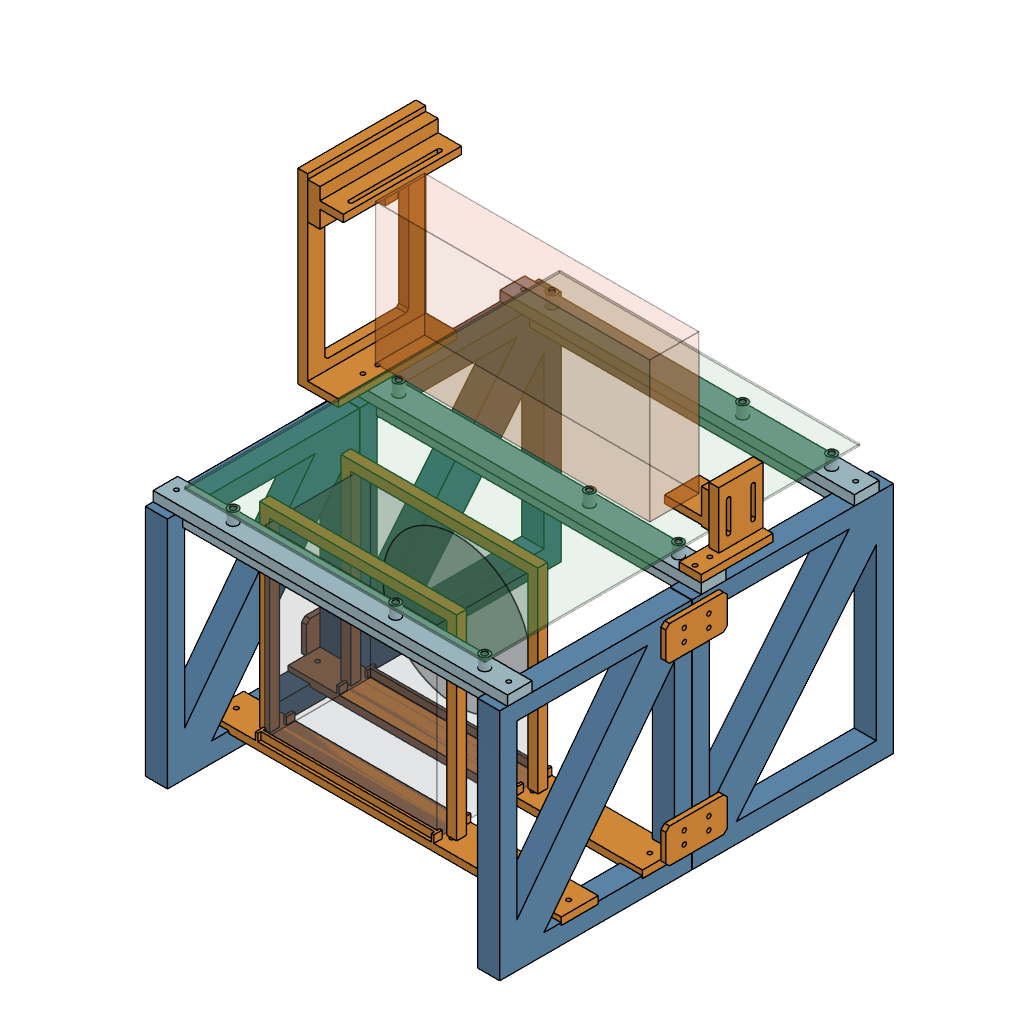
ATX_Desk_v01 (Autodesk Fusion 360 design; units mm, degrees)
part number: 2026-10-20-22-05-08-730
part number: 2026-10-20-22-08-08-339
part number: 2026-10-20-22-08-09-316
part number: 2026-10-20-22-08-11-193
part number: 2026-10-20-22-08-14-444
part number: 2026-10-20-22-08-18-650
part number: 2026-10-20-22-08-21-543
part number: 2026-10-20-22-08-24-691
part number: 2026-10-20-22-08-28-165
part number: 2026-10-20-22-08-32-235
part number: 2026-10-20-22-08-43-731
part number: 2026-10-20-22-09-05-620
part number: 2026-10-20-22-09-23-823
part number: 2026-10-20-22-09-44-105
part number: 2026-10-20-22-09-50-238
part number: 2026-10-20-22-10-13-900
part number: 2026-10-20-22-10-20-773
part number: 2026-10-20-22-10-46-637
part number: 2026-10-20-22-11-06-448
part number: 2026-10-20-22-11-11-779
part number: 2026-10-20-22-11-40-530
part number: 2026-10-20-22-11-51-657
part number: 2026-10-20-22-12-25-247
part number: 2026-10-20-22-12-53-814
part number: 2026-10-20-22-12-58-404
part number: 2026-10-20-22-13-02-654
Autodesk Fusion 360 part; units mm, degrees
(part 1 of 2)
ref_plane "工作平面1" through (0, 0, 0) normal (0, 0, 1) x (1, 0, 0) in component "01_Side_L_rear"
sketch "草图1" plane through (0, 0, 0) normal (0, 0, 1) x (1, 0, 0) in component "01_Side_L_rear"
  line L0 (-22, -10) -> (-4, -10)
  line L1 (-4, -10) -> (-4, 146)
  line L2 (-4, 146) -> (-22, 146)
  line L3 (-22, 146) -> (-22, -10)
extrude "18 mm triangulated side panel" add sketch "草图1" along normal blind 190 makes body 1 in component "01_Side_L_rear"
ref_plane "工作平面2" through (-22, 0, 0) normal (1, 0, 0) x (0, 1, 0) in component "01_Side_L_rear"
sketch "草图2" plane through (-22, 0, 0) normal (1, 0, 0) x (0, 0, -1) in component "01_Side_L_rear"
  line L0 (-36, 4) -> (-176, 4)
  line L1 (-176, 4) -> (-176, 110)
  line L2 (-176, 110) -> (-36, 4)
extrude "Upper lightening window" cut sketch "草图2" along normal blind 18 bodies 1 in component "01_Side_L_rear"
ref_plane "工作平面3" through (-22, 0, 0) normal (1, 0, 0) x (0, 1, 0) in component "01_Side_L_rear"
sketch "草图3" plane through (-22, 0, 0) normal (1, 0, 0) x (0, 0, -1) in component "01_Side_L_rear"
  line L0 (-16, 26) -> (-16, 132)
  line L1 (-16, 132) -> (-154, 132)
  line L2 (-154, 132) -> (-16, 26)
extrude "Lower lightening window" cut sketch "草图3" along normal blind 18 bodies 1 in component "01_Side_L_rear"
ref_plane "工作平面4" through (0, 0, 185.3) normal (0, 0, 1) x (1, 0, 0) in component "01_Side_L_rear"
sketch "草图4" plane through (0, 0, 185.3) normal (0, 0, 1) x (1, 0, 0) in component "01_Side_L_rear"
  circle A0 centre (-13, 6.35) radius 2.35
extrude "M3 heat insert pocket" cut sketch "草图4" along normal blind 4.7 bodies 1 in component "01_Side_L_rear"
ref_plane "工作平面5" through (0, 0, 9.3) normal (0, 0, 1) x (1, 0, 0) in component "01_Side_L_rear"
sketch "草图5" plane through (0, 0, 9.3) normal (0, 0, 1) x (1, 0, 0) in component "01_Side_L_rear"
  circle A0 centre (-13, 55) radius 2.35
extrude "M3 heat insert pocket (1)" cut sketch "草图5" along normal blind 4.7 bodies 1 in component "01_Side_L_rear"
ref_plane "工作平面6" through (0, 0, 9.3) normal (0, 0, 1) x (1, 0, 0) in component "01_Side_L_rear"
sketch "草图6" plane through (0, 0, 9.3) normal (0, 0, 1) x (1, 0, 0) in component "01_Side_L_rear"
  circle A0 centre (-13, 121) radius 2.35
extrude "M3 heat insert pocket (2)" cut sketch "草图6" along normal blind 4.7 bodies 1 in component "01_Side_L_rear"
ref_plane "工作平面7" through (-22, 0, 0) normal (1, 0, 0) x (0, 1, 0) in component "01_Side_L_rear"
sketch "草图7" plane through (-22, 0, 0) normal (1, 0, 0) x (0, 0, -1) in component "01_Side_L_rear"
  circle A0 centre (-25, 136) radius 2.35
extrude "M3 long insert side pocket" cut sketch "草图7" along normal blind 8.2 bodies 1 in component "01_Side_L_rear"
ref_plane "工作平面8" through (-22, 0, 0) normal (1, 0, 0) x (0, 1, 0) in component "01_Side_L_rear"
sketch "草图8" plane through (-22, 0, 0) normal (1, 0, 0) x (0, 0, -1) in component "01_Side_L_rear"
  circle A0 centre (-35, 136) radius 2.35
extrude "M3 long insert side pocket (1)" cut sketch "草图8" along normal blind 8.2 bodies 1 in component "01_Side_L_rear"
ref_plane "工作平面9" through (-22, 0, 0) normal (1, 0, 0) x (0, 1, 0) in component "01_Side_L_rear"
sketch "草图9" plane through (-22, 0, 0) normal (1, 0, 0) x (0, 0, -1) in component "01_Side_L_rear"
  circle A0 centre (-167.5, 136) radius 2.35
extrude "M3 long insert side pocket (2)" cut sketch "草图9" along normal blind 8.2 bodies 1 in component "01_Side_L_rear"
ref_plane "工作平面10" through (-22, 0, 0) normal (1, 0, 0) x (0, 1, 0) in component "01_Side_L_rear"
sketch "草图10" plane through (-22, 0, 0) normal (1, 0, 0) x (0, 0, -1) in component "01_Side_L_rear"
  circle A0 centre (-177.5, 136) radius 2.35
extrude "M3 long insert side pocket (3)" cut sketch "草图10" along normal blind 8.2 bodies 1 in component "01_Side_L_rear"
ref_plane "工作平面1" through (0, 0, 0) normal (0, 0, 1) x (1, 0, 0) in component "01_Side_L_front"
sketch "草图1 (2)" plane through (0, 0, 0) normal (0, 0, 1) x (1, 0, 0) in component "01_Side_L_front"
  line L0 (-22, 146.4) -> (-4, 146.4)
  line L1 (-4, 146.4) -> (-4, 310)
  line L2 (-4, 310) -> (-22, 310)
  line L3 (-22, 310) -> (-22, 146.4)
extrude "18 mm triangulated side panel'" add sketch "草图1 (2)" along normal blind 190 separate body makes body 2 in component "01_Side_L_front"
ref_plane "工作平面2" through (-22, 0, 0) normal (1, 0, 0) x (0, 1, 0) in component "01_Side_L_front"
sketch "草图2 (2)" plane through (-22, 0, 0) normal (1, 0, 0) x (0, 0, -1) in component "01_Side_L_front"
  line L0 (-36, 160.4) -> (-176, 160.4)
  line L1 (-176, 160.4) -> (-176, 274)
  line L2 (-176, 274) -> (-36, 160.4)
extrude "Upper lightening window'" cut sketch "草图2 (2)" along normal blind 18 bodies 2 in component "01_Side_L_front"
ref_plane "工作平面3" through (-22, 0, 0) normal (1, 0, 0) x (0, 1, 0) in component "01_Side_L_front"
sketch "草图3 (2)" plane through (-22, 0, 0) normal (1, 0, 0) x (0, 0, -1) in component "01_Side_L_front"
  line L0 (-16, 182.4) -> (-16, 296)
  line L1 (-16, 296) -> (-154, 296)
  line L2 (-154, 296) -> (-16, 182.4)
extrude "Lower lightening window'" cut sketch "草图3 (2)" along normal blind 18 bodies 2 in component "01_Side_L_front"
ref_plane "工作平面4" through (0, 0, 185.3) normal (0, 0, 1) x (1, 0, 0) in component "01_Side_L_front"
sketch "草图4 (2)" plane through (0, 0, 185.3) normal (0, 0, 1) x (1, 0, 0) in component "01_Side_L_front"
  circle A0 centre (-13, 163.83) radius 2.35
extrude "M3 heat insert pocket'" cut sketch "草图4 (2)" along normal blind 4.7 bodies 2 in component "01_Side_L_front"
ref_plane "工作平面5" through (0, 0, 185.3) normal (0, 0, 1) x (1, 0, 0) in component "01_Side_L_front"
sketch "草图5 (2)" plane through (0, 0, 185.3) normal (0, 0, 1) x (1, 0, 0) in component "01_Side_L_front"
  circle A0 centre (-13, 288.29) radius 2.35
extrude "M3 heat insert pocket (1)'" cut sketch "草图5 (2)" along normal blind 4.7 bodies 2 in component "01_Side_L_front"
ref_plane "工作平面6" through (-22, 0, 0) normal (1, 0, 0) x (0, 1, 0) in component "01_Side_L_front"
sketch "草图6 (2)" plane through (-22, 0, 0) normal (1, 0, 0) x (0, 0, -1) in component "01_Side_L_front"
  circle A0 centre (-25, 156) radius 2.35
extrude "M3 long insert side pocket'" cut sketch "草图6 (2)" along normal blind 8.2 bodies 2 in component "01_Side_L_front"
ref_plane "工作平面7" through (-22, 0, 0) normal (1, 0, 0) x (0, 1, 0) in component "01_Side_L_front"
sketch "草图7 (2)" plane through (-22, 0, 0) normal (1, 0, 0) x (0, 0, -1) in component "01_Side_L_front"
  circle A0 centre (-35, 156) radius 2.35
extrude "M3 long insert side pocket (1)'" cut sketch "草图7 (2)" along normal blind 8.2 bodies 2 in component "01_Side_L_front"
ref_plane "工作平面8" through (-22, 0, 0) normal (1, 0, 0) x (0, 1, 0) in component "01_Side_L_front"
sketch "草图8 (2)" plane through (-22, 0, 0) normal (1, 0, 0) x (0, 0, -1) in component "01_Side_L_front"
  circle A0 centre (-167.5, 156) radius 2.35
extrude "M3 long insert side pocket (2)'" cut sketch "草图8 (2)" along normal blind 8.2 bodies 2 in component "01_Side_L_front"
ref_plane "工作平面9" through (-22, 0, 0) normal (1, 0, 0) x (0, 1, 0) in component "01_Side_L_front"
sketch "草图9 (2)" plane through (-22, 0, 0) normal (1, 0, 0) x (0, 0, -1) in component "01_Side_L_front"
  circle A0 centre (-177.5, 156) radius 2.35
extrude "M3 long insert side pocket (3)'" cut sketch "草图9 (2)" along normal blind 8.2 bodies 2 in component "01_Side_L_front"
ref_plane "工作平面1" through (0, 0, 0) normal (0, 0, 1) x (1, 0, 0) in component "01_Side_R_rear"
sketch "草图1 (3)" plane through (0, 0, 0) normal (0, 0, 1) x (1, 0, 0) in component "01_Side_R_rear"
  line L0 (248, -10) -> (266, -10)
  line L1 (266, -10) -> (266, 146)
  line L2 (266, 146) -> (248, 146)
  line L3 (248, 146) -> (248, -10)
extrude "18 mm triangulated side panel''" add sketch "草图1 (3)" along normal blind 190 separate body makes body 3 in component "01_Side_R_rear"
ref_plane "工作平面2" through (248, 0, 0) normal (1, 0, 0) x (0, 1, 0) in component "01_Side_R_rear"
sketch "草图2 (3)" plane through (248, 0, 0) normal (1, 0, 0) x (0, 0, -1) in component "01_Side_R_rear"
  line L0 (-36, 4) -> (-176, 4)
  line L1 (-176, 4) -> (-176, 110)
  line L2 (-176, 110) -> (-36, 4)
extrude "Upper lightening window''" cut sketch "草图2 (3)" along normal blind 18 bodies 3 in component "01_Side_R_rear"
ref_plane "工作平面3" through (248, 0, 0) normal (1, 0, 0) x (0, 1, 0) in component "01_Side_R_rear"
sketch "草图3 (3)" plane through (248, 0, 0) normal (1, 0, 0) x (0, 0, -1) in component "01_Side_R_rear"
  line L0 (-16, 26) -> (-16, 132)
  line L1 (-16, 132) -> (-154, 132)
  line L2 (-154, 132) -> (-16, 26)
extrude "Lower lightening window''" cut sketch "草图3 (3)" along normal blind 18 bodies 3 in component "01_Side_R_rear"
ref_plane "工作平面4" through (0, 0, 185.3) normal (0, 0, 1) x (1, 0, 0) in component "01_Side_R_rear"
sketch "草图4 (3)" plane through (0, 0, 185.3) normal (0, 0, 1) x (1, 0, 0) in component "01_Side_R_rear"
  circle A0 centre (257, 6.35) radius 2.35
extrude "M3 heat insert pocket''" cut sketch "草图4 (3)" along normal blind 4.7 bodies 3 in component "01_Side_R_rear"
ref_plane "工作平面5" through (0, 0, 9.3) normal (0, 0, 1) x (1, 0, 0) in component "01_Side_R_rear"
sketch "草图5 (3)" plane through (0, 0, 9.3) normal (0, 0, 1) x (1, 0, 0) in component "01_Side_R_rear"
  circle A0 centre (257, 55) radius 2.35
extrude "M3 heat insert pocket (1)''" cut sketch "草图5 (3)" along normal blind 4.7 bodies 3 in component "01_Side_R_rear"
ref_plane "工作平面6" through (0, 0, 9.3) normal (0, 0, 1) x (1, 0, 0) in component "01_Side_R_rear"
sketch "草图6 (3)" plane through (0, 0, 9.3) normal (0, 0, 1) x (1, 0, 0) in component "01_Side_R_rear"
  circle A0 centre (257, 121) radius 2.35
extrude "M3 heat insert pocket (2)'" cut sketch "草图6 (3)" along normal blind 4.7 bodies 3 in component "01_Side_R_rear"
ref_plane "工作平面7" through (257.8, 0, 0) normal (1, 0, 0) x (0, 1, 0) in component "01_Side_R_rear"
sketch "草图7 (3)" plane through (257.8, 0, 0) normal (1, 0, 0) x (0, 0, -1) in component "01_Side_R_rear"
  circle A0 centre (-25, 136) radius 2.35
extrude "M3 long insert side pocket''" cut sketch "草图7 (3)" along normal blind 8.2 bodies 3 in component "01_Side_R_rear"
ref_plane "工作平面8" through (257.8, 0, 0) normal (1, 0, 0) x (0, 1, 0) in component "01_Side_R_rear"
sketch "草图8 (3)" plane through (257.8, 0, 0) normal (1, 0, 0) x (0, 0, -1) in component "01_Side_R_rear"
  circle A0 centre (-35, 136) radius 2.35
extrude "M3 long insert side pocket (1)''" cut sketch "草图8 (3)" along normal blind 8.2 bodies 3 in component "01_Side_R_rear"
ref_plane "工作平面9" through (257.8, 0, 0) normal (1, 0, 0) x (0, 1, 0) in component "01_Side_R_rear"
sketch "草图9 (3)" plane through (257.8, 0, 0) normal (1, 0, 0) x (0, 0, -1) in component "01_Side_R_rear"
  circle A0 centre (-167.5, 136) radius 2.35
extrude "M3 long insert side pocket (2)''" cut sketch "草图9 (3)" along normal blind 8.2 bodies 3 in component "01_Side_R_rear"
ref_plane "工作平面10" through (257.8, 0, 0) normal (1, 0, 0) x (0, 1, 0) in component "01_Side_R_rear"
sketch "草图10 (2)" plane through (257.8, 0, 0) normal (1, 0, 0) x (0, 0, -1) in component "01_Side_R_rear"
  circle A0 centre (-177.5, 136) radius 2.35
extrude "M3 long insert side pocket (3)''" cut sketch "草图10 (2)" along normal blind 8.2 bodies 3 in component "01_Side_R_rear"
ref_plane "工作平面1" through (0, 0, 0) normal (0, 0, 1) x (1, 0, 0) in component "01_Side_R_front"
sketch "草图1 (4)" plane through (0, 0, 0) normal (0, 0, 1) x (1, 0, 0) in component "01_Side_R_front"
  line L0 (248, 146.4) -> (266, 146.4)
  line L1 (266, 146.4) -> (266, 310)
  line L2 (266, 310) -> (248, 310)
  line L3 (248, 310) -> (248, 146.4)
extrude "18 mm triangulated side panel'''" add sketch "草图1 (4)" along normal blind 190 separate body makes body 4 in component "01_Side_R_front"
ref_plane "工作平面2" through (248, 0, 0) normal (1, 0, 0) x (0, 1, 0) in component "01_Side_R_front"
sketch "草图2 (4)" plane through (248, 0, 0) normal (1, 0, 0) x (0, 0, -1) in component "01_Side_R_front"
  line L0 (-36, 160.4) -> (-176, 160.4)
  line L1 (-176, 160.4) -> (-176, 274)
  line L2 (-176, 274) -> (-36, 160.4)
extrude "Upper lightening window'''" cut sketch "草图2 (4)" along normal blind 18 bodies 4 in component "01_Side_R_front"
ref_plane "工作平面3" through (248, 0, 0) normal (1, 0, 0) x (0, 1, 0) in component "01_Side_R_front"
sketch "草图3 (4)" plane through (248, 0, 0) normal (1, 0, 0) x (0, 0, -1) in component "01_Side_R_front"
  line L0 (-16, 182.4) -> (-16, 296)
  line L1 (-16, 296) -> (-154, 296)
  line L2 (-154, 296) -> (-16, 182.4)
extrude "Lower lightening window'''" cut sketch "草图3 (4)" along normal blind 18 bodies 4 in component "01_Side_R_front"
ref_plane "工作平面4" through (0, 0, 185.3) normal (0, 0, 1) x (1, 0, 0) in component "01_Side_R_front"
sketch "草图4 (4)" plane through (0, 0, 185.3) normal (0, 0, 1) x (1, 0, 0) in component "01_Side_R_front"
  circle A0 centre (257, 163.83) radius 2.35
extrude "M3 heat insert pocket'''" cut sketch "草图4 (4)" along normal blind 4.7 bodies 4 in component "01_Side_R_front"
ref_plane "工作平面5" through (0, 0, 185.3) normal (0, 0, 1) x (1, 0, 0) in component "01_Side_R_front"
sketch "草图5 (4)" plane through (0, 0, 185.3) normal (0, 0, 1) x (1, 0, 0) in component "01_Side_R_front"
  circle A0 centre (257, 288.29) radius 2.35
extrude "M3 heat insert pocket (1)'''" cut sketch "草图5 (4)" along normal blind 4.7 bodies 4 in component "01_Side_R_front"
ref_plane "工作平面6" through (257.8, 0, 0) normal (1, 0, 0) x (0, 1, 0) in component "01_Side_R_front"
sketch "草图6 (4)" plane through (257.8, 0, 0) normal (1, 0, 0) x (0, 0, -1) in component "01_Side_R_front"
  circle A0 centre (-25, 156) radius 2.35
extrude "M3 long insert side pocket'''" cut sketch "草图6 (4)" along normal blind 8.2 bodies 4 in component "01_Side_R_front"
ref_plane "工作平面7" through (257.8, 0, 0) normal (1, 0, 0) x (0, 1, 0) in component "01_Side_R_front"
sketch "草图7 (4)" plane through (257.8, 0, 0) normal (1, 0, 0) x (0, 0, -1) in component "01_Side_R_front"
  circle A0 centre (-35, 156) radius 2.35
extrude "M3 long insert side pocket (1)'''" cut sketch "草图7 (4)" along normal blind 8.2 bodies 4 in component "01_Side_R_front"
ref_plane "工作平面8" through (257.8, 0, 0) normal (1, 0, 0) x (0, 1, 0) in component "01_Side_R_front"
sketch "草图8 (4)" plane through (257.8, 0, 0) normal (1, 0, 0) x (0, 0, -1) in component "01_Side_R_front"
  circle A0 centre (-167.5, 156) radius 2.35
extrude "M3 long insert side pocket (2)'''" cut sketch "草图8 (4)" along normal blind 8.2 bodies 4 in component "01_Side_R_front"
ref_plane "工作平面9" through (257.8, 0, 0) normal (1, 0, 0) x (0, 1, 0) in component "01_Side_R_front"
sketch "草图9 (4)" plane through (257.8, 0, 0) normal (1, 0, 0) x (0, 0, -1) in component "01_Side_R_front"
  circle A0 centre (-177.5, 156) radius 2.35
extrude "M3 long insert side pocket (3)'''" cut sketch "草图9 (4)" along normal blind 8.2 bodies 4 in component "01_Side_R_front"
ref_plane "工作平面1" through (-26, 0, 0) normal (1, 0, 0) x (0, 1, 0) in component "02_Splice_L_low"
sketch "草图1 (5)" plane through (-26, 0, 0) normal (1, 0, 0) x (0, 0, -1) in component "02_Splice_L_low"
  line L0 (-19, 121) -> (-16, 124)
  line L1 (-16, 124) -> (-16, 168)
  line L2 (-16, 168) -> (-19, 171)
  line L3 (-19, 171) -> (-41, 171)
  line L4 (-41, 171) -> (-44, 168)
  line L5 (-44, 168) -> (-44, 124)
  line L6 (-44, 124) -> (-41, 121)
  line L7 (-41, 121) -> (-19, 121)
extrude "Chamfered splice plate" add sketch "草图1 (5)" along normal blind 4 separate body makes body 5 in component "02_Splice_L_low"
ref_plane "工作平面2" through (-26, 0, 0) normal (1, 0, 0) x (0, 1, 0) in component "02_Splice_L_low"
sketch "草图2 (5)" plane through (-26, 0, 0) normal (1, 0, 0) x (0, 0, -1) in component "02_Splice_L_low"
  circle A0 centre (-25, 136) radius 1.7
extrude "M3x12 splice screw clearance" cut sketch "草图2 (5)" along normal blind 4 bodies 5 in component "02_Splice_L_low"
ref_plane "工作平面3" through (-26, 0, 0) normal (1, 0, 0) x (0, 1, 0) in component "02_Splice_L_low"
sketch "草图3 (5)" plane through (-26, 0, 0) normal (1, 0, 0) x (0, 0, -1) in component "02_Splice_L_low"
  circle A0 centre (-35, 136) radius 1.7
extrude "M3x12 splice screw clearance (1)" cut sketch "草图3 (5)" along normal blind 4 bodies 5 in component "02_Splice_L_low"
ref_plane "工作平面4" through (-26, 0, 0) normal (1, 0, 0) x (0, 1, 0) in component "02_Splice_L_low"
sketch "草图4 (5)" plane through (-26, 0, 0) normal (1, 0, 0) x (0, 0, -1) in component "02_Splice_L_low"
  circle A0 centre (-25, 156) radius 1.7
extrude "M3x12 splice screw clearance (2)" cut sketch "草图4 (5)" along normal blind 4 bodies 5 in component "02_Splice_L_low"
ref_plane "工作平面5" through (-26, 0, 0) normal (1, 0, 0) x (0, 1, 0) in component "02_Splice_L_low"
sketch "草图5 (5)" plane through (-26, 0, 0) normal (1, 0, 0) x (0, 0, -1) in component "02_Splice_L_low"
  circle A0 centre (-35, 156) radius 1.7
extrude "M3x12 splice screw clearance (3)" cut sketch "草图5 (5)" along normal blind 4 bodies 5 in component "02_Splice_L_low"
ref_plane "工作平面1" through (-26, 0, 0) normal (1, 0, 0) x (0, 1, 0) in component "02_Splice_L_high"
sketch "草图1 (6)" plane through (-26, 0, 0) normal (1, 0, 0) x (0, 0, -1) in component "02_Splice_L_high"
  line L0 (-161.5, 121) -> (-158.5, 124)
  line L1 (-158.5, 124) -> (-158.5, 168)
  line L2 (-158.5, 168) -> (-161.5, 171)
  line L3 (-161.5, 171) -> (-183.5, 171)
  line L4 (-183.5, 171) -> (-186.5, 168)
  line L5 (-186.5, 168) -> (-186.5, 124)
  line L6 (-186.5, 124) -> (-183.5, 121)
  line L7 (-183.5, 121) -> (-161.5, 121)
extrude "Chamfered splice plate'" add sketch "草图1 (6)" along normal blind 4 separate body makes body 6 in component "02_Splice_L_high"
ref_plane "工作平面2" through (-26, 0, 0) normal (1, 0, 0) x (0, 1, 0) in component "02_Splice_L_high"
sketch "草图2 (6)" plane through (-26, 0, 0) normal (1, 0, 0) x (0, 0, -1) in component "02_Splice_L_high"
  circle A0 centre (-167.5, 136) radius 1.7
extrude "M3x12 splice screw clearance'" cut sketch "草图2 (6)" along normal blind 4 bodies 6 in component "02_Splice_L_high"
ref_plane "工作平面3" through (-26, 0, 0) normal (1, 0, 0) x (0, 1, 0) in component "02_Splice_L_high"
sketch "草图3 (6)" plane through (-26, 0, 0) normal (1, 0, 0) x (0, 0, -1) in component "02_Splice_L_high"
  circle A0 centre (-177.5, 136) radius 1.7
extrude "M3x12 splice screw clearance (1)'" cut sketch "草图3 (6)" along normal blind 4 bodies 6 in component "02_Splice_L_high"
ref_plane "工作平面4" through (-26, 0, 0) normal (1, 0, 0) x (0, 1, 0) in component "02_Splice_L_high"
sketch "草图4 (6)" plane through (-26, 0, 0) normal (1, 0, 0) x (0, 0, -1) in component "02_Splice_L_high"
  circle A0 centre (-167.5, 156) radius 1.7
extrude "M3x12 splice screw clearance (2)'" cut sketch "草图4 (6)" along normal blind 4 bodies 6 in component "02_Splice_L_high"
ref_plane "工作平面5" through (-26, 0, 0) normal (1, 0, 0) x (0, 1, 0) in component "02_Splice_L_high"
sketch "草图5 (6)" plane through (-26, 0, 0) normal (1, 0, 0) x (0, 0, -1) in component "02_Splice_L_high"
  circle A0 centre (-177.5, 156) radius 1.7
extrude "M3x12 splice screw clearance (3)'" cut sketch "草图5 (6)" along normal blind 4 bodies 6 in component "02_Splice_L_high"
ref_plane "工作平面1" through (266, 0, 0) normal (1, 0, 0) x (0, 1, 0) in component "02_Splice_R_low"
sketch "草图1 (7)" plane through (266, 0, 0) normal (1, 0, 0) x (0, 0, -1) in component "02_Splice_R_low"
  line L0 (-19, 121) -> (-16, 124)
  line L1 (-16, 124) -> (-16, 168)
  line L2 (-16, 168) -> (-19, 171)
  line L3 (-19, 171) -> (-41, 171)
  line L4 (-41, 171) -> (-44, 168)
  line L5 (-44, 168) -> (-44, 124)
  line L6 (-44, 124) -> (-41, 121)
  line L7 (-41, 121) -> (-19, 121)
extrude "Chamfered splice plate''" add sketch "草图1 (7)" along normal blind 4 separate body makes body 7 in component "02_Splice_R_low"
ref_plane "工作平面2" through (266, 0, 0) normal (1, 0, 0) x (0, 1, 0) in component "02_Splice_R_low"
sketch "草图2 (7)" plane through (266, 0, 0) normal (1, 0, 0) x (0, 0, -1) in component "02_Splice_R_low"
  circle A0 centre (-25, 136) radius 1.7
extrude "M3x12 splice screw clearance''" cut sketch "草图2 (7)" along normal blind 4 bodies 7 in component "02_Splice_R_low"
ref_plane "工作平面3" through (266, 0, 0) normal (1, 0, 0) x (0, 1, 0) in component "02_Splice_R_low"
sketch "草图3 (7)" plane through (266, 0, 0) normal (1, 0, 0) x (0, 0, -1) in component "02_Splice_R_low"
  circle A0 centre (-35, 136) radius 1.7
extrude "M3x12 splice screw clearance (1)''" cut sketch "草图3 (7)" along normal blind 4 bodies 7 in component "02_Splice_R_low"
ref_plane "工作平面4" through (266, 0, 0) normal (1, 0, 0) x (0, 1, 0) in component "02_Splice_R_low"
sketch "草图4 (7)" plane through (266, 0, 0) normal (1, 0, 0) x (0, 0, -1) in component "02_Splice_R_low"
  circle A0 centre (-25, 156) radius 1.7
extrude "M3x12 splice screw clearance (2)''" cut sketch "草图4 (7)" along normal blind 4 bodies 7 in component "02_Splice_R_low"
ref_plane "工作平面5" through (266, 0, 0) normal (1, 0, 0) x (0, 1, 0) in component "02_Splice_R_low"
sketch "草图5 (7)" plane through (266, 0, 0) normal (1, 0, 0) x (0, 0, -1) in component "02_Splice_R_low"
  circle A0 centre (-35, 156) radius 1.7
extrude "M3x12 splice screw clearance (3)''" cut sketch "草图5 (7)" along normal blind 4 bodies 7 in component "02_Splice_R_low"
ref_plane "工作平面1" through (266, 0, 0) normal (1, 0, 0) x (0, 1, 0) in component "02_Splice_R_high"
sketch "草图1 (8)" plane through (266, 0, 0) normal (1, 0, 0) x (0, 0, -1) in component "02_Splice_R_high"
  line L0 (-161.5, 121) -> (-158.5, 124)
  line L1 (-158.5, 124) -> (-158.5, 168)
  line L2 (-158.5, 168) -> (-161.5, 171)
  line L3 (-161.5, 171) -> (-183.5, 171)
  line L4 (-183.5, 171) -> (-186.5, 168)
  line L5 (-186.5, 168) -> (-186.5, 124)
  line L6 (-186.5, 124) -> (-183.5, 121)
  line L7 (-183.5, 121) -> (-161.5, 121)
extrude "Chamfered splice plate'''" add sketch "草图1 (8)" along normal blind 4 separate body makes body 8 in component "02_Splice_R_high"
ref_plane "工作平面2" through (266, 0, 0) normal (1, 0, 0) x (0, 1, 0) in component "02_Splice_R_high"
sketch "草图2 (8)" plane through (266, 0, 0) normal (1, 0, 0) x (0, 0, -1) in component "02_Splice_R_high"
  circle A0 centre (-167.5, 136) radius 1.7
extrude "M3x12 splice screw clearance'''" cut sketch "草图2 (8)" along normal blind 4 bodies 8 in component "02_Splice_R_high"
ref_plane "工作平面3" through (266, 0, 0) normal (1, 0, 0) x (0, 1, 0) in component "02_Splice_R_high"
sketch "草图3 (8)" plane through (266, 0, 0) normal (1, 0, 0) x (0, 0, -1) in component "02_Splice_R_high"
  circle A0 centre (-177.5, 136) radius 1.7
extrude "M3x12 splice screw clearance (1)'''" cut sketch "草图3 (8)" along normal blind 4 bodies 8 in component "02_Splice_R_high"
ref_plane "工作平面4" through (266, 0, 0) normal (1, 0, 0) x (0, 1, 0) in component "02_Splice_R_high"
sketch "草图4 (8)" plane through (266, 0, 0) normal (1, 0, 0) x (0, 0, -1) in component "02_Splice_R_high"
  circle A0 centre (-167.5, 156) radius 1.7
extrude "M3x12 splice screw clearance (2)'''" cut sketch "草图4 (8)" along normal blind 4 bodies 8 in component "02_Splice_R_high"
ref_plane "工作平面5" through (266, 0, 0) normal (1, 0, 0) x (0, 1, 0) in component "02_Splice_R_high"
sketch "草图5 (8)" plane through (266, 0, 0) normal (1, 0, 0) x (0, 0, -1) in component "02_Splice_R_high"
  circle A0 centre (-177.5, 156) radius 1.7
extrude "M3x12 splice screw clearance (3)'''" cut sketch "草图5 (8)" along normal blind 4 bodies 8 in component "02_Splice_R_high"
ref_plane "工作平面1" through (0, 0, 190) normal (0, 0, 1) x (1, 0, 0) in component "03_BoardBeam_CPU"
sketch "草图1 (9)" plane through (0, 0, 190) normal (0, 0, 1) x (1, 0, 0) in component "03_BoardBeam_CPU"
  line L0 (-22, -3.65) -> (266, -3.65)
  line L1 (266, -3.65) -> (266, 16.35)
  line L2 (266, 16.35) -> (-22, 16.35)
  line L3 (-22, 16.35) -> (-22, -3.65)
extrude "8 mm top flange" add sketch "草图1 (9)" along normal blind 8 separate body makes body 9 in component "03_BoardBeam_CPU"
ref_plane "工作平面2" through (0, 0, 178) normal (0, 0, 1) x (1, 0, 0) in component "03_BoardBeam_CPU"
sketch "草图2 (9)" plane through (0, 0, 178) normal (0, 0, 1) x (1, 0, 0) in component "03_BoardBeam_CPU"
  line L0 (-4, 2.35) -> (248, 2.35)
  line L1 (248, 2.35) -> (248, 10.35)
  line L2 (248, 10.35) -> (-4, 10.35)
  line L3 (-4, 10.35) -> (-4, 2.35)
extrude "12 mm underside stiffening rib" add sketch "草图2 (9)" along normal blind 12 bodies 9 in component "03_BoardBeam_CPU"
ref_plane "工作平面3" through (-4, 0, 0) normal (1, 0, 0) x (0, 1, 0) in component "03_BoardBeam_CPU"
sketch "草图3 (9)" plane through (-4, 0, 0) normal (1, 0, 0) x (0, 0, -1) in component "03_BoardBeam_CPU"
  line L0 (-184, 2.35) -> (-184, 10.35)
  line L1 (-184, 10.35) -> (-190, 16.35)
  line L2 (-190, 16.35) -> (-190, -3.65)
  line L3 (-190, -3.65) -> (-184, 2.35)
extrude "45 degree flange support transitions" add sketch "草图3 (9)" along normal blind 252 bodies 9 in component "03_BoardBeam_CPU"
ref_plane "工作平面4" through (0, 0, 190) normal (0, 0, 1) x (1, 0, 0) in component "03_BoardBeam_CPU"
sketch "草图4 (9)" plane through (0, 0, 190) normal (0, 0, 1) x (1, 0, 0) in component "03_BoardBeam_CPU"
  circle A0 centre (-13, 6.35) radius 1.7
extrude "M3x12 to side frame" cut sketch "草图4 (9)" along normal blind 8 bodies 9 in component "03_BoardBeam_CPU"
ref_plane "工作平面5" through (0, 0, 190) normal (0, 0, 1) x (1, 0, 0) in component "03_BoardBeam_CPU"
sketch "草图5 (9)" plane through (0, 0, 190) normal (0, 0, 1) x (1, 0, 0) in component "03_BoardBeam_CPU"
  circle A0 centre (257, 6.35) radius 1.7
extrude "M3x12 to side frame (1)" cut sketch "草图5 (9)" along normal blind 8 bodies 9 in component "03_BoardBeam_CPU"
ref_plane "工作平面6" through (0, 0, 198) normal (0, 0, 1) x (1, 0, 0) in component "03_BoardBeam_CPU"
sketch "草图6 (5)" plane through (0, 0, 198) normal (0, 0, 1) x (1, 0, 0) in component "03_BoardBeam_CPU"
  circle A0 centre (33.02, 6.35) radius 4
extrude "10 mm motherboard standoff F" add sketch "草图6 (5)" along normal blind 10 bodies 9 in component "03_BoardBeam_CPU"
ref_plane "工作平面7" through (0, 0, 203.1) normal (0, 0, 1) x (1, 0, 0) in component "03_BoardBeam_CPU"
sketch "草图7 (5)" plane through (0, 0, 203.1) normal (0, 0, 1) x (1, 0, 0) in component "03_BoardBeam_CPU"
  circle A0 centre (33.02, 6.35) radius 2.35
extrude "M3 heat insert pocket''''" cut sketch "草图7 (5)" along normal blind 4.7 bodies 9 in component "03_BoardBeam_CPU"
ref_plane "工作平面8" through (0, 0, 200) normal (0, 0, 1) x (1, 0, 0) in component "03_BoardBeam_CPU"
sketch "草图8 (5)" plane through (0, 0, 200) normal (0, 0, 1) x (1, 0, 0) in component "03_BoardBeam_CPU"
  circle A0 centre (33.02, 6.35) radius 1.6
extrude "Screw tip relief F" cut sketch "草图8 (5)" along normal blind 3.1 bodies 9 in component "03_BoardBeam_CPU"
ref_plane "工作平面9" through (0, 0, 198) normal (0, 0, 1) x (1, 0, 0) in component "03_BoardBeam_CPU"
sketch "草图9 (5)" plane through (0, 0, 198) normal (0, 0, 1) x (1, 0, 0) in component "03_BoardBeam_CPU"
  circle A0 centre (165.1, 6.35) radius 4
extrude "10 mm motherboard standoff J" add sketch "草图9 (5)" along normal blind 10 bodies 9 in component "03_BoardBeam_CPU"
ref_plane "工作平面10" through (0, 0, 203.1) normal (0, 0, 1) x (1, 0, 0) in component "03_BoardBeam_CPU"
sketch "草图10 (3)" plane through (0, 0, 203.1) normal (0, 0, 1) x (1, 0, 0) in component "03_BoardBeam_CPU"
  circle A0 centre (165.1, 6.35) radius 2.35
extrude "M3 heat insert pocket (1)''''" cut sketch "草图10 (3)" along normal blind 4.7 bodies 9 in component "03_BoardBeam_CPU"
ref_plane "工作平面11" through (0, 0, 200) normal (0, 0, 1) x (1, 0, 0) in component "03_BoardBeam_CPU"
sketch "草图11" plane through (0, 0, 200) normal (0, 0, 1) x (1, 0, 0) in component "03_BoardBeam_CPU"
  circle A0 centre (165.1, 6.35) radius 1.6
extrude "Screw tip relief J" cut sketch "草图11" along normal blind 3.1 bodies 9 in component "03_BoardBeam_CPU"
ref_plane "工作平面12" through (0, 0, 198) normal (0, 0, 1) x (1, 0, 0) in component "03_BoardBeam_CPU"
sketch "草图12" plane through (0, 0, 198) normal (0, 0, 1) x (1, 0, 0) in component "03_BoardBeam_CPU"
  circle A0 centre (237.49, 6.35) radius 4
extrude "10 mm motherboard standoff M" add sketch "草图12" along normal blind 10 bodies 9 in component "03_BoardBeam_CPU"
ref_plane "工作平面13" through (0, 0, 203.1) normal (0, 0, 1) x (1, 0, 0) in component "03_BoardBeam_CPU"
sketch "草图13" plane through (0, 0, 203.1) normal (0, 0, 1) x (1, 0, 0) in component "03_BoardBeam_CPU"
  circle A0 centre (237.49, 6.35) radius 2.35
extrude "M3 heat insert pocket (2)''" cut sketch "草图13" along normal blind 4.7 bodies 9 in component "03_BoardBeam_CPU"
ref_plane "工作平面14" through (0, 0, 200) normal (0, 0, 1) x (1, 0, 0) in component "03_BoardBeam_CPU"
sketch "草图14" plane through (0, 0, 200) normal (0, 0, 1) x (1, 0, 0) in component "03_BoardBeam_CPU"
  circle A0 centre (237.49, 6.35) radius 1.6
extrude "Screw tip relief M" cut sketch "草图14" along normal blind 3.1 bodies 9 in component "03_BoardBeam_CPU"
ref_plane "工作平面1" through (0, 0, 190) normal (0, 0, 1) x (1, 0, 0) in component "03_BoardBeam_MID"
sketch "草图1 (10)" plane through (0, 0, 190) normal (0, 0, 1) x (1, 0, 0) in component "03_BoardBeam_MID"
  line L0 (-22, 153.83) -> (266, 153.83)
  line L1 (266, 153.83) -> (266, 173.83)
  line L2 (266, 173.83) -> (-22, 173.83)
  line L3 (-22, 173.83) -> (-22, 153.83)
extrude "8 mm top flange'" add sketch "草图1 (10)" along normal blind 8 separate body makes body 10 in component "03_BoardBeam_MID"
ref_plane "工作平面2" through (0, 0, 178) normal (0, 0, 1) x (1, 0, 0) in component "03_BoardBeam_MID"
sketch "草图2 (10)" plane through (0, 0, 178) normal (0, 0, 1) x (1, 0, 0) in component "03_BoardBeam_MID"
  line L0 (-4, 159.83) -> (248, 159.83)
  line L1 (248, 159.83) -> (248, 167.83)
  line L2 (248, 167.83) -> (-4, 167.83)
  line L3 (-4, 167.83) -> (-4, 159.83)
extrude "12 mm underside stiffening rib'" add sketch "草图2 (10)" along normal blind 12 bodies 10 in component "03_BoardBeam_MID"
ref_plane "工作平面3" through (-4, 0, 0) normal (1, 0, 0) x (0, 1, 0) in component "03_BoardBeam_MID"
sketch "草图3 (10)" plane through (-4, 0, 0) normal (1, 0, 0) x (0, 0, -1) in component "03_BoardBeam_MID"
  line L0 (-184, 159.83) -> (-184, 167.83)
  line L1 (-184, 167.83) -> (-190, 173.83)
  line L2 (-190, 173.83) -> (-190, 153.83)
  line L3 (-190, 153.83) -> (-184, 159.83)
extrude "45 degree flange support transitions'" add sketch "草图3 (10)" along normal blind 252 bodies 10 in component "03_BoardBeam_MID"
ref_plane "工作平面4" through (0, 0, 190) normal (0, 0, 1) x (1, 0, 0) in component "03_BoardBeam_MID"
sketch "草图4 (10)" plane through (0, 0, 190) normal (0, 0, 1) x (1, 0, 0) in component "03_BoardBeam_MID"
  circle A0 centre (-13, 163.83) radius 1.7
extrude "M3x12 to side frame'" cut sketch "草图4 (10)" along normal blind 8 bodies 10 in component "03_BoardBeam_MID"
ref_plane "工作平面5" through (0, 0, 190) normal (0, 0, 1) x (1, 0, 0) in component "03_BoardBeam_MID"
sketch "草图5 (10)" plane through (0, 0, 190) normal (0, 0, 1) x (1, 0, 0) in component "03_BoardBeam_MID"
  circle A0 centre (257, 163.83) radius 1.7
extrude "M3x12 to side frame (1)'" cut sketch "草图5 (10)" along normal blind 8 bodies 10 in component "03_BoardBeam_MID"
ref_plane "工作平面6" through (0, 0, 198) normal (0, 0, 1) x (1, 0, 0) in component "03_BoardBeam_MID"
sketch "草图6 (6)" plane through (0, 0, 198) normal (0, 0, 1) x (1, 0, 0) in component "03_BoardBeam_MID"
  circle A0 centre (10.16, 163.83) radius 4
extrude "10 mm motherboard standoff C" add sketch "草图6 (6)" along normal blind 10 bodies 10 in component "03_BoardBeam_MID"
ref_plane "工作平面7" through (0, 0, 203.1) normal (0, 0, 1) x (1, 0, 0) in component "03_BoardBeam_MID"
sketch "草图7 (6)" plane through (0, 0, 203.1) normal (0, 0, 1) x (1, 0, 0) in component "03_BoardBeam_MID"
  circle A0 centre (10.16, 163.83) radius 2.35
extrude "M3 heat insert pocket'''''" cut sketch "草图7 (6)" along normal blind 4.7 bodies 10 in component "03_BoardBeam_MID"
ref_plane "工作平面8" through (0, 0, 200) normal (0, 0, 1) x (1, 0, 0) in component "03_BoardBeam_MID"
sketch "草图8 (6)" plane through (0, 0, 200) normal (0, 0, 1) x (1, 0, 0) in component "03_BoardBeam_MID"
  circle A0 centre (10.16, 163.83) radius 1.6
extrude "Screw tip relief C" cut sketch "草图8 (6)" along normal blind 3.1 bodies 10 in component "03_BoardBeam_MID"
ref_plane "工作平面9" through (0, 0, 198) normal (0, 0, 1) x (1, 0, 0) in component "03_BoardBeam_MID"
sketch "草图9 (6)" plane through (0, 0, 198) normal (0, 0, 1) x (1, 0, 0) in component "03_BoardBeam_MID"
  circle A0 centre (165.1, 163.83) radius 4
extrude "10 mm motherboard standoff H" add sketch "草图9 (6)" along normal blind 10 bodies 10 in component "03_BoardBeam_MID"
ref_plane "工作平面10" through (0, 0, 203.1) normal (0, 0, 1) x (1, 0, 0) in component "03_BoardBeam_MID"
sketch "草图10 (4)" plane through (0, 0, 203.1) normal (0, 0, 1) x (1, 0, 0) in component "03_BoardBeam_MID"
  circle A0 centre (165.1, 163.83) radius 2.35
extrude "M3 heat insert pocket (1)'''''" cut sketch "草图10 (4)" along normal blind 4.7 bodies 10 in component "03_BoardBeam_MID"
ref_plane "工作平面11" through (0, 0, 200) normal (0, 0, 1) x (1, 0, 0) in component "03_BoardBeam_MID"
sketch "草图11 (2)" plane through (0, 0, 200) normal (0, 0, 1) x (1, 0, 0) in component "03_BoardBeam_MID"
  circle A0 centre (165.1, 163.83) radius 1.6
extrude "Screw tip relief H" cut sketch "草图11 (2)" along normal blind 3.1 bodies 10 in component "03_BoardBeam_MID"
ref_plane "工作平面12" through (0, 0, 198) normal (0, 0, 1) x (1, 0, 0) in component "03_BoardBeam_MID"
sketch "草图12 (2)" plane through (0, 0, 198) normal (0, 0, 1) x (1, 0, 0) in component "03_BoardBeam_MID"
  circle A0 centre (237.49, 163.83) radius 4
extrude "10 mm motherboard standoff L" add sketch "草图12 (2)" along normal blind 10 bodies 10 in component "03_BoardBeam_MID"
ref_plane "工作平面13" through (0, 0, 203.1) normal (0, 0, 1) x (1, 0, 0) in component "03_BoardBeam_MID"
sketch "草图13 (2)" plane through (0, 0, 203.1) normal (0, 0, 1) x (1, 0, 0) in component "03_BoardBeam_MID"
  circle A0 centre (237.49, 163.83) radius 2.35
extrude "M3 heat insert pocket (2)'''" cut sketch "草图13 (2)" along normal blind 4.7 bodies 10 in component "03_BoardBeam_MID"
ref_plane "工作平面14" through (0, 0, 200) normal (0, 0, 1) x (1, 0, 0) in component "03_BoardBeam_MID"
sketch "草图14 (2)" plane through (0, 0, 200) normal (0, 0, 1) x (1, 0, 0) in component "03_BoardBeam_MID"
  circle A0 centre (237.49, 163.83) radius 1.6
extrude "Screw tip relief L" cut sketch "草图14 (2)" along normal blind 3.1 bodies 10 in component "03_BoardBeam_MID"
ref_plane "工作平面15" through (0, 0, 193.3) normal (0, 0, 1) x (1, 0, 0) in component "03_BoardBeam_MID"
sketch "草图15" plane through (0, 0, 193.3) normal (0, 0, 1) x (1, 0, 0) in component "03_BoardBeam_MID"
  circle A0 centre (-13, 157.83) radius 2.35
extrude "M3 heat insert pocket (3)" cut sketch "草图15" along normal blind 4.7 bodies 10 in component "03_BoardBeam_MID"
ref_plane "工作平面16" through (0, 0, 193.3) normal (0, 0, 1) x (1, 0, 0) in component "03_BoardBeam_MID"
sketch "草图16" plane through (0, 0, 193.3) normal (0, 0, 1) x (1, 0, 0) in component "03_BoardBeam_MID"
  circle A0 centre (-13, 169.83) radius 2.35
extrude "M3 heat insert pocket (4)" cut sketch "草图16" along normal blind 4.7 bodies 10 in component "03_BoardBeam_MID"
ref_plane "工作平面17" through (0, 0, 193.3) normal (0, 0, 1) x (1, 0, 0) in component "03_BoardBeam_MID"
sketch "草图17" plane through (0, 0, 193.3) normal (0, 0, 1) x (1, 0, 0) in component "03_BoardBeam_MID"
  circle A0 centre (257, 157.83) radius 2.35
extrude "M3 heat insert pocket (5)" cut sketch "草图17" along normal blind 4.7 bodies 10 in component "03_BoardBeam_MID"
ref_plane "工作平面18" through (0, 0, 193.3) normal (0, 0, 1) x (1, 0, 0) in component "03_BoardBeam_MID"
sketch "草图18" plane through (0, 0, 193.3) normal (0, 0, 1) x (1, 0, 0) in component "03_BoardBeam_MID"
  circle A0 centre (257, 169.83) radius 2.35
extrude "M3 heat insert pocket (6)" cut sketch "草图18" along normal blind 4.7 bodies 10 in component "03_BoardBeam_MID"
ref_plane "工作平面1" through (0, 0, 190) normal (0, 0, 1) x (1, 0, 0) in component "03_BoardBeam_PCI"
sketch "草图1 (11)" plane through (0, 0, 190) normal (0, 0, 1) x (1, 0, 0) in component "03_BoardBeam_PCI"
  line L0 (-22, 278.29) -> (266, 278.29)
  line L1 (266, 278.29) -> (266, 298.29)
  line L2 (266, 298.29) -> (-22, 298.29)
  line L3 (-22, 298.29) -> (-22, 278.29)
extrude "8 mm top flange''" add sketch "草图1 (11)" along normal blind 8 separate body makes body 11 in component "03_BoardBeam_PCI"
ref_plane "工作平面2" through (0, 0, 178) normal (0, 0, 1) x (1, 0, 0) in component "03_BoardBeam_PCI"
sketch "草图2 (11)" plane through (0, 0, 178) normal (0, 0, 1) x (1, 0, 0) in component "03_BoardBeam_PCI"
  line L0 (-4, 284.29) -> (248, 284.29)
  line L1 (248, 284.29) -> (248, 292.29)
  line L2 (248, 292.29) -> (-4, 292.29)
  line L3 (-4, 292.29) -> (-4, 284.29)
extrude "12 mm underside stiffening rib''" add sketch "草图2 (11)" along normal blind 12 bodies 11 in component "03_BoardBeam_PCI"
ref_plane "工作平面3" through (-4, 0, 0) normal (1, 0, 0) x (0, 1, 0) in component "03_BoardBeam_PCI"
sketch "草图3 (11)" plane through (-4, 0, 0) normal (1, 0, 0) x (0, 0, -1) in component "03_BoardBeam_PCI"
  line L0 (-184, 284.29) -> (-184, 292.29)
  line L1 (-184, 292.29) -> (-190, 298.29)
  line L2 (-190, 298.29) -> (-190, 278.29)
  line L3 (-190, 278.29) -> (-184, 284.29)
extrude "45 degree flange support transitions''" add sketch "草图3 (11)" along normal blind 252 bodies 11 in component "03_BoardBeam_PCI"
ref_plane "工作平面4" through (0, 0, 190) normal (0, 0, 1) x (1, 0, 0) in component "03_BoardBeam_PCI"
sketch "草图4 (11)" plane through (0, 0, 190) normal (0, 0, 1) x (1, 0, 0) in component "03_BoardBeam_PCI"
  circle A0 centre (-13, 288.29) radius 1.7
extrude "M3x12 to side frame''" cut sketch "草图4 (11)" along normal blind 8 bodies 11 in component "03_BoardBeam_PCI"
ref_plane "工作平面5" through (0, 0, 190) normal (0, 0, 1) x (1, 0, 0) in component "03_BoardBeam_PCI"
sketch "草图5 (11)" plane through (0, 0, 190) normal (0, 0, 1) x (1, 0, 0) in component "03_BoardBeam_PCI"
  circle A0 centre (257, 288.29) radius 1.7
extrude "M3x12 to side frame (1)''" cut sketch "草图5 (11)" along normal blind 8 bodies 11 in component "03_BoardBeam_PCI"
ref_plane "工作平面6" through (0, 0, 198) normal (0, 0, 1) x (1, 0, 0) in component "03_BoardBeam_PCI"
sketch "草图6 (7)" plane through (0, 0, 198) normal (0, 0, 1) x (1, 0, 0) in component "03_BoardBeam_PCI"
  circle A0 centre (10.16, 288.29) radius 4
extrude "10 mm motherboard standoff A" add sketch "草图6 (7)" along normal blind 10 bodies 11 in component "03_BoardBeam_PCI"
ref_plane "工作平面7" through (0, 0, 203.1) normal (0, 0, 1) x (1, 0, 0) in component "03_BoardBeam_PCI"
sketch "草图7 (7)" plane through (0, 0, 203.1) normal (0, 0, 1) x (1, 0, 0) in component "03_BoardBeam_PCI"
  circle A0 centre (10.16, 288.29) radius 2.35
extrude "M3 heat insert pocket''''''" cut sketch "草图7 (7)" along normal blind 4.7 bodies 11 in component "03_BoardBeam_PCI"
ref_plane "工作平面8" through (0, 0, 200) normal (0, 0, 1) x (1, 0, 0) in component "03_BoardBeam_PCI"
sketch "草图8 (7)" plane through (0, 0, 200) normal (0, 0, 1) x (1, 0, 0) in component "03_BoardBeam_PCI"
  circle A0 centre (10.16, 288.29) radius 1.6
extrude "Screw tip relief A" cut sketch "草图8 (7)" along normal blind 3.1 bodies 11 in component "03_BoardBeam_PCI"
ref_plane "工作平面9" through (0, 0, 198) normal (0, 0, 1) x (1, 0, 0) in component "03_BoardBeam_PCI"
sketch "草图9 (7)" plane through (0, 0, 198) normal (0, 0, 1) x (1, 0, 0) in component "03_BoardBeam_PCI"
  circle A0 centre (165.1, 288.29) radius 4
extrude "10 mm motherboard standoff G" add sketch "草图9 (7)" along normal blind 10 bodies 11 in component "03_BoardBeam_PCI"
ref_plane "工作平面10" through (0, 0, 203.1) normal (0, 0, 1) x (1, 0, 0) in component "03_BoardBeam_PCI"
sketch "草图10 (5)" plane through (0, 0, 203.1) normal (0, 0, 1) x (1, 0, 0) in component "03_BoardBeam_PCI"
  circle A0 centre (165.1, 288.29) radius 2.35
extrude "M3 heat insert pocket (1)''''''" cut sketch "草图10 (5)" along normal blind 4.7 bodies 11 in component "03_BoardBeam_PCI"
ref_plane "工作平面11" through (0, 0, 200) normal (0, 0, 1) x (1, 0, 0) in component "03_BoardBeam_PCI"
sketch "草图11 (3)" plane through (0, 0, 200) normal (0, 0, 1) x (1, 0, 0) in component "03_BoardBeam_PCI"
  circle A0 centre (165.1, 288.29) radius 1.6
extrude "Screw tip relief G" cut sketch "草图11 (3)" along normal blind 3.1 bodies 11 in component "03_BoardBeam_PCI"
ref_plane "工作平面12" through (0, 0, 198) normal (0, 0, 1) x (1, 0, 0) in component "03_BoardBeam_PCI"
sketch "草图12 (3)" plane through (0, 0, 198) normal (0, 0, 1) x (1, 0, 0) in component "03_BoardBeam_PCI"
  circle A0 centre (237.49, 288.29) radius 4
extrude "10 mm motherboard standoff K" add sketch "草图12 (3)" along normal blind 10 bodies 11 in component "03_BoardBeam_PCI"
ref_plane "工作平面13" through (0, 0, 203.1) normal (0, 0, 1) x (1, 0, 0) in component "03_BoardBeam_PCI"
sketch "草图13 (3)" plane through (0, 0, 203.1) normal (0, 0, 1) x (1, 0, 0) in component "03_BoardBeam_PCI"
  circle A0 centre (237.49, 288.29) radius 2.35
extrude "M3 heat insert pocket (2)''''" cut sketch "草图13 (3)" along normal blind 4.7 bodies 11 in component "03_BoardBeam_PCI"
ref_plane "工作平面14" through (0, 0, 200) normal (0, 0, 1) x (1, 0, 0) in component "03_BoardBeam_PCI"
sketch "草图14 (3)" plane through (0, 0, 200) normal (0, 0, 1) x (1, 0, 0) in component "03_BoardBeam_PCI"
  circle A0 centre (237.49, 288.29) radius 1.6
extrude "Screw tip relief K" cut sketch "草图14 (3)" along normal blind 3.1 bodies 11 in component "03_BoardBeam_PCI"
ref_plane "工作平面1" through (0, 0, 14) normal (0, 0, 1) x (1, 0, 0) in component "04_PSU_Shelf_rear"
sketch "草图1 (12)" plane through (0, 0, 14) normal (0, 0, 1) x (1, 0, 0) in component "04_PSU_Shelf_rear"
  line L0 (-22, 40) -> (266, 40)
  line L1 (266, 40) -> (266, 70)
  line L2 (266, 70) -> (-22, 70)
  line L3 (-22, 70) -> (-22, 40)
extrude "PSU bottom support rail" add sketch "草图1 (12)" along normal blind 6 separate body makes body 12 in component "04_PSU_Shelf_rear"
ref_plane "工作平面2" through (0, 0, 14) normal (0, 0, 1) x (1, 0, 0) in component "04_PSU_Shelf_rear"
sketch "草图2 (12)" plane through (0, 0, 14) normal (0, 0, 1) x (1, 0, 0) in component "04_PSU_Shelf_rear"
  circle A0 centre (-13, 55) radius 1.7
extrude "M3x10 shelf to frame" cut sketch "草图2 (12)" along normal blind 6 bodies 1 in component "01_Side_L_rear"
extrude "拉伸2" cut sketch "草图2 (12)" along normal blind 6 bodies 12 in component "04_PSU_Shelf_rear"
ref_plane "工作平面3" through (0, 0, 14) normal (0, 0, 1) x (1, 0, 0) in component "04_PSU_Shelf_rear"
sketch "草图3 (12)" plane through (0, 0, 14) normal (0, 0, 1) x (1, 0, 0) in component "04_PSU_Shelf_rear"
  circle A0 centre (257, 55) radius 1.7
extrude "M3x10 shelf to frame'" cut sketch "草图3 (12)" along normal blind 6 bodies 3 in component "01_Side_R_rear"
extrude "拉伸3" cut sketch "草图3 (12)" along normal blind 6 bodies 12 in component "04_PSU_Shelf_rear"
ref_plane "工作平面4" through (0, 0, 14) normal (0, 0, 1) x (1, 0, 0) in component "04_PSU_Shelf_rear"
sketch "草图4 (12)" plane through (0, 0, 14) normal (0, 0, 1) x (1, 0, 0) in component "04_PSU_Shelf_rear"
  circle A0 centre (14, 51) radius 1.7
extrude "Hoop position adjustment end 1" cut sketch "草图4 (12)" along normal blind 6 bodies 12 in component "04_PSU_Shelf_rear"
ref_plane "工作平面5" through (0, 0, 14) normal (0, 0, 1) x (1, 0, 0) in component "04_PSU_Shelf_rear"
sketch "草图5 (12)" plane through (0, 0, 14) normal (0, 0, 1) x (1, 0, 0) in component "04_PSU_Shelf_rear"
  circle A0 centre (14, 59) radius 1.7
extrude "Hoop position adjustment end 2" cut sketch "草图5 (12)" along normal blind 6 bodies 12 in component "04_PSU_Shelf_rear"
ref_plane "工作平面6" through (0, 0, 14) normal (0, 0, 1) x (1, 0, 0) in component "04_PSU_Shelf_rear"
sketch "草图6 (8)" plane through (0, 0, 14) normal (0, 0, 1) x (1, 0, 0) in component "04_PSU_Shelf_rear"
  line L0 (12.3, 51) -> (15.7, 51)
  line L1 (15.7, 51) -> (15.7, 59)
  line L2 (15.7, 59) -> (12.3, 59)
  line L3 (12.3, 59) -> (12.3, 51)
extrude "Hoop position adjustment bridge" cut sketch "草图6 (8)" along normal blind 6 bodies 12 in component "04_PSU_Shelf_rear"
ref_plane "工作平面7" through (0, 0, 14) normal (0, 0, 1) x (1, 0, 0) in component "04_PSU_Shelf_rear"
sketch "草图7 (8)" plane through (0, 0, 14) normal (0, 0, 1) x (1, 0, 0) in component "04_PSU_Shelf_rear"
  circle A0 centre (166, 51) radius 1.7
extrude "Hoop position adjustment end 1 (1)" cut sketch "草图7 (8)" along normal blind 6 bodies 12 in component "04_PSU_Shelf_rear"
ref_plane "工作平面8" through (0, 0, 14) normal (0, 0, 1) x (1, 0, 0) in component "04_PSU_Shelf_rear"
sketch "草图8 (8)" plane through (0, 0, 14) normal (0, 0, 1) x (1, 0, 0) in component "04_PSU_Shelf_rear"
  circle A0 centre (166, 59) radius 1.7
extrude "Hoop position adjustment end 2 (1)" cut sketch "草图8 (8)" along normal blind 6 bodies 12 in component "04_PSU_Shelf_rear"
ref_plane "工作平面9" through (0, 0, 14) normal (0, 0, 1) x (1, 0, 0) in component "04_PSU_Shelf_rear"
sketch "草图9 (8)" plane through (0, 0, 14) normal (0, 0, 1) x (1, 0, 0) in component "04_PSU_Shelf_rear"
  line L0 (164.3, 51) -> (167.7, 51)
  line L1 (167.7, 51) -> (167.7, 59)
  line L2 (167.7, 59) -> (164.3, 59)
  line L3 (164.3, 59) -> (164.3, 51)
extrude "Hoop position adjustment bridge (1)" cut sketch "草图9 (8)" along normal blind 6 bodies 12 in component "04_PSU_Shelf_rear"
ref_plane "工作平面10" through (0, 0, 20) normal (0, 0, 1) x (1, 0, 0) in component "04_PSU_Shelf_rear"
sketch "草图10 (6)" plane through (0, 0, 20) normal (0, 0, 1) x (1, 0, 0) in component "04_PSU_Shelf_rear"
  line L0 (17.5, 40) -> (19.5, 40)
  line L1 (19.5, 40) -> (19.5, 70)
  line L2 (19.5, 70) -> (17.5, 70)
  line L3 (17.5, 70) -> (17.5, 40)
extrude "PSU fore aft locating stop" add sketch "草图10 (6)" along normal blind 6 bodies 12 in component "04_PSU_Shelf_rear"
ref_plane "工作平面11" through (0, 0, 20) normal (0, 0, 1) x (1, 0, 0) in component "04_PSU_Shelf_rear"
sketch "草图11 (4)" plane through (0, 0, 20) normal (0, 0, 1) x (1, 0, 0) in component "04_PSU_Shelf_rear"
  line L0 (160.5, 40) -> (162.5, 40)
  line L1 (162.5, 40) -> (162.5, 70)
  line L2 (162.5, 70) -> (160.5, 70)
  line L3 (160.5, 70) -> (160.5, 40)
extrude "PSU fore aft locating stop (1)" add sketch "草图11 (4)" along normal blind 6 bodies 12 in component "04_PSU_Shelf_rear"
ref_plane "工作平面12" through (0, 0, 20) normal (0, 0, 1) x (1, 0, 0) in component "04_PSU_Shelf_rear"
sketch "草图12 (4)" plane through (0, 0, 20) normal (0, 0, 1) x (1, 0, 0) in component "04_PSU_Shelf_rear"
  line L0 (19.5, 42.5) -> (160.5, 42.5)
  line L1 (160.5, 42.5) -> (160.5, 44.5)
  line L2 (160.5, 44.5) -> (19.5, 44.5)
  line L3 (19.5, 44.5) -> (19.5, 42.5)
extrude "PSU side locating lip" add sketch "草图12 (4)" along normal blind 6 bodies 12 in component "04_PSU_Shelf_rear"
ref_plane "工作平面1" through (0, -51, 0) normal (0, 1, 0) x (0, 0, 1) in component "05_PSU_Hoop_rear"
sketch "草图1 (13)" plane through (0, -51, 0) normal (0, 1, 0) x (1, 0, 0) in component "05_PSU_Hoop_rear"
  line L0 (10, -20, 102) -> (18, -20, 102)
  line L1 (18, -20, 102) -> (18, -171, 102)
  line L2 (18, -171, 102) -> (162, -171, 102)
  line L3 (162, -171, 102) -> (162, -20, 102)
  line L4 (162, -20, 102) -> (170, -20, 102)
  line L5 (170, -20, 102) -> (170, -179, 102)
  line L6 (170, -179, 102) -> (10, -179, 102)
  line L7 (10, -179, 102) -> (10, -20, 102)
extrude "Removable PSU retaining hoop" add sketch "草图1 (13)" along normal blind 8 separate body contours L0 L1 L2 L3 L4 L5 L6 L7 in plane through (0, 51, 0) normal (0, 1, 0) makes body 13 in component "05_PSU_Hoop_rear"
ref_plane "工作平面2" through (0, 0, 20) normal (0, 0, 1) x (1, 0, 0) in component "05_PSU_Hoop_rear"
sketch "草图2 (13)" plane through (0, 0, 20) normal (0, 0, 1) x (1, 0, 0) in component "05_PSU_Hoop_rear"
  circle A0 centre (14, 55) radius 2.35
extrude "M3 long insert from underside" cut sketch "草图2 (13)" along normal blind 8.2 bodies 13 in component "05_PSU_Hoop_rear"
ref_plane "工作平面3" through (0, 0, 20) normal (0, 0, 1) x (1, 0, 0) in component "05_PSU_Hoop_rear"
sketch "草图3 (13)" plane through (0, 0, 20) normal (0, 0, 1) x (1, 0, 0) in component "05_PSU_Hoop_rear"
  circle A0 centre (166, 55) radius 2.35
extrude "M3 long insert from underside (1)" cut sketch "草图3 (13)" along normal blind 8.2 bodies 13 in component "05_PSU_Hoop_rear"
ref_plane "工作平面1" through (0, 0, 14) normal (0, 0, 1) x (1, 0, 0) in component "04_PSU_Shelf_front"
sketch "草图1 (14)" plane through (0, 0, 14) normal (0, 0, 1) x (1, 0, 0) in component "04_PSU_Shelf_front"
  line L0 (-22, 106) -> (266, 106)
  line L1 (266, 106) -> (266, 136)
  line L2 (266, 136) -> (-22, 136)
  line L3 (-22, 136) -> (-22, 106)